LidFace (Autodesk Fusion 360 design; units mm, degrees)
Autodesk Fusion 360 part; units mm, degrees
sketch "Sketch1" plane through (0, 0, 0) normal (0, 1, 0) x (1, 0, 0)
  circle A0 centre (0, 0) radius 10.65
  dimension "d1" = 21.3
  constraint coincident A0.centre origin
  measures "d1" diameter of A0
extrude "Extrude1" add sketch "Sketch1" along normal blind 29.6 makes body 1
sketch "Sketch2" plane through (0, 29.6, 0) normal (0, 1, 0) x (-1, 0, 0)
  circle A0 centre (0, 0) radius 10.65
  circle A1 centre (0, 0) radius 7.15
  dimension "d4" = 14.3
  constraint coincident A0.centre A1.centre
  measures "d4" diameter of A1
extrude "Extrude2" cut sketch "Sketch2" against normal blind 27.6 contours A1 bodies 1
sketch "Sketch3" plane through (0, 29.6, 0) normal (0, 1, 0) x (-1, 0, 0)
  circle A0 centre (0, 0) radius 7.15
  circle A1 centre (0, 0) radius 10.65
  line L0 (0, -10.65) -> (2.4, -10.65)
  line L1 (0, -10.65) -> (-2.4, -10.65)
  line L2 (2.4, -10.65) -> (2.4, -7.1491)
  line L3 (-2.4, -10.65) -> (-2.4, -8)
  line L4 (2.4, -10.65) -> (2.4, -15.65)
  line L5 (-2.4, -10.65) -> (-2.4, -15.65)
  line L6 (2.4, -15.65) -> (-2.4, -15.65)
  dimension "d7" = 2.4
  dimension "d8" = 2.4
  dimension "d9" = 5
  dimension "d10" = 5
  constraint coincident A1 L0.start
  constraint horizontal L0
  constraint horizontal L1
  constraint perpendicular L0 L2
  constraint perpendicular L1 L3
  constraint vertical L4
  constraint vertical L5
  measures "d7" distance of L0.start L0.end
  measures "d8" distance of L0.start L1.end
  measures "d9" distance of L0.end L4.end
  measures "d10" distance of L1.end L5.end
extrude "Extrude3" add sketch "Sketch3" against normal blind 5 contours A1 L1 L3 | A1 L0 L2 | L0 L1 L4 L5 L6 bodies 1
sketch "Sketch4" plane through (2.4, 0, 0) normal (1, 0, 0) x (0, 0, -1)
  line L0 (15.65, 29.6) -> (10.3761, 29.6)
  line L1 (10.3761, 29.6) -> (10.3761, 24.6)
  line L2 (10.3761, 24.6) -> (15.65, 24.6)
  line L3 (15.65, 24.6) -> (15.65, 29.6)
  line L4 (13.013, 29.6) -> (13.013, 27.1)
  circle A0 centre (13.013, 27.1) radius 2.5
  circle A1 centre (13.013, 27.1) radius 1.95
  dimension "d13" = 2.5
  dimension "d14" = 5
  dimension "d15" = 3.9
  constraint midpoint L0 L4.start
  constraint vertical L4
  constraint coincident L4.end A0.centre
  constraint concentric A0 A1
  measures "d13" distance of L4.start L4.end
  measures "d14" diameter of A0
  measures "d15" diameter of A1
sphere "SpherePrimitive1" add diameter 3.9 placed x (0, 0, -1) y (0, 1, 0) z (1, 0, 0) at (2.4, 27.1, -13.013) bodies 1
sketch "Sketch5" plane through (-2.4, 0, 0) normal (-1, 0, 0) x (0, 0, 1)
  line L0 (-10.3761, 29.6) -> (-15.65, 29.6)
  line L1 (-15.65, 29.6) -> (-15.65, 24.6)
  line L2 (-15.65, 24.6) -> (-10.3761, 24.6)
  line L3 (-10.3761, 24.6) -> (-10.3761, 29.6)
  circle A0 centre (-13.013, 27.1) radius 1.95
  point P0 (-13.013, 27.1)
  dimension "d17" = 3.9
  constraint coincident P0 A0.centre
  measures "d17" diameter of A0
sphere "SpherePrimitive2" add diameter 3.9 placed x (0, 0, 1) y (0, 1, 0) z (-1, 0, 0) at (-2.4, 27.1, -13.013) bodies 1
fillet "Fillet1" radius 2.5 2 edges at (0, 29.6, -15.65) (0, 24.6, -15.65) on bodies 1
fillet "Fillet2" radius 2.5 1 edges at (0, 24.6, -10.65) on bodies 1
sketch "Sketch6" plane through (0, 0, 0) normal (0, -1, 0) x (1, 0, 0)
  circle A0 centre (0, 0) radius 10.65
  line L0 (-10.65, 0) -> (10.65, 0)
  line L1 (10.65, 0) -> (10.65, -17.8532)
  line L2 (10.65, -17.8532) -> (-10.65, -17.8532)
  line L3 (-10.65, -17.8532) -> (-10.65, 0)
  point P0 (-10.65, 0)
  dimension "d21" = 21.3
  constraint horizontal L0
  constraint vertical L1
  constraint horizontal L2
  constraint vertical L3
  constraint coincident P0 L0.start
  measures "d21" distance of P0 L0.end
extrude "Extrude4" cut sketch "Sketch6" against normal blind 37 contours A0 L1 L2 L3 | A0 L0 picked at (3.0909, -3.0462) bodies 1
sketch "Sketch7" plane through (0, 0, 0) normal (0, 0, -1) x (-1, 0, 0)
  line L0 (10.65, 29.6) -> (7.15, 29.6)
  line L1 (7.15, 29.6) -> (7.15, 2)
  line L2 (7.15, 2) -> (-7.15, 2)
  line L3 (-10.65, 0) -> (10.65, 0)
  line L4 (10.65, 0) -> (10.65, 29.6)
  line L5 (-10.65, 0) -> (-10.65, 29.6)
  line L6 (-10.65, 0) -> (-10.65, 14.8)
  line L7 (-15.65, 17.475) -> (-10.65, 17.475)
  line L8 (-15.65, 12.125) -> (-10.65, 12.0997)
  line L9 (-15.65, 17.475) -> (-15.65, 19.975)
  line L10 (-15.65, 19.975) -> (-10.65, 19.975)
  line L11 (-15.65, 12.125) -> (-15.65, 9.625)
  line L12 (-15.65, 9.625) -> (-10.65, 9.625)
  point P0 (-10.65, 29.6)
  dimension "d65" = 2.5
  dimension "d66" = 2.5
  dimension "d67" = 5
  constraint coincident L3.start L5.start
  constraint coincident P0 L5.end
  constraint midpoint L5 L6.end
  constraint coincident L5 L7.end
  constraint perpendicular L5 L7
  constraint coincident L6 L8.end
  constraint coincident L5 L10.end
  constraint perpendicular L5 L10
  constraint vertical L11
  constraint horizontal L12
  measures "d65" distance of L7.start L9.end
  measures "d66" distance of L8.start L11.end
  measures "d67" distance of L11.end L12.end
extrude "Extrude7" add sketch "Sketch7" along normal blind 2.5 and the other way blind 2.5 separate body makes body 2 at (12.3167, 12.1081, -0.8333) makes body 3 at (13.9833, 17.475, 0.8333)
sketch "Sketch13" plane through (10.65, 0, 0) normal (-1, 0, 0) x (0, 0, 1)
  line L0 (2.5, 19.975) -> (-2.5, 19.975)
  line L1 (-2.5, 19.975) -> (-2.5, 17.475)
  line L2 (-2.5, 17.475) -> (2.5, 17.475)
  line L3 (2.5, 17.475) -> (2.5, 19.975)
extrude "Extrude8" add sketch "Sketch13" 1 faces at (10.65, 11.2748, -0.8333) along normal blind 1.5 on bodies 2 bodies 2 1 3
sketch "Sketch14" plane through (0, 0, 0) normal (0, 0, -1) x (-1, 0, 0)
  line L0 (-9.15, 9.625) -> (-10.65, 9.625)
  line L1 (-10.65, 9.625) -> (-10.65, 0)
  line L2 (-10.65, 0) -> (10.65, 0)
  line L3 (10.65, 0) -> (10.65, 29.6)
  line L4 (10.65, 29.6) -> (7.15, 29.6)
  line L5 (7.15, 29.6) -> (7.15, 2)
  line L6 (7.15, 2) -> (-7.15, 2)
  line L7 (-7.15, 2) -> (-7.15, 29.6)
  line L8 (-7.15, 29.6) -> (-10.65, 29.6)
  line L9 (-10.65, 29.6) -> (-10.65, 19.975)
  line L10 (-10.65, 19.975) -> (-9.15, 19.975)
  line L11 (-9.15, 19.975) -> (-9.15, 17.475)
  line L12 (-9.15, 17.475) -> (-10.65, 17.475)
  line L13 (-10.65, 17.475) -> (-10.65, 12.0997)
  line L14 (-10.65, 12.0997) -> (-9.15, 12.0997)
  line L15 (-9.15, 12.0997) -> (-9.15, 9.625)
  line L16 (-10.65, 17.475) -> (-10.65, 19.975)
  line L17 (-10.65, 12.0997) -> (-10.65, 9.625)
  constraint coincident L12.end L13.start
  constraint coincident L9.end L10.start
  constraint coincident L13.end L14.start
  constraint coincident L0.end L1.start
extrude "Extrude9" cut sketch "Sketch14" along normal blind 4 bodies 2
sketch "Sketch15" plane through (-0.0609, 12.0456, 0) normal (-0.005055, 0.999987, 0) x (0, 0, 1)
  line L0 (2.5, 15.7111) -> (-2.5, 15.7111)
  line L1 (-2.5, 15.7111) -> (-2.5, 10.711)
  line L2 (-2.5, 10.711) -> (0, 10.711)
  line L3 (0, 10.711) -> (2.5, 10.711)
  line L4 (2.5, 10.711) -> (2.5, 15.7111)
  line L5 (0, 15.7111) -> (0, 10.7995)
  line L6 (-2.5, 13.2111) -> (2.5, 13.2111)
  circle A0 centre (0, 13.2111) radius 2
  circle A1 centre (0, 13.2111) radius 2
  point P0 (0, 10.7995)
  dimension "d77" = 4
  constraint midpoint L0 L5.start
  constraint coincident P0 L5.end
  constraint midpoint L1 L6.start
  constraint midpoint L4 L6.end
  constraint midpoint L6 A0.centre
  constraint concentric A0 A1
  measures "d77" diameter of A0
sketch "Sketch16" plane through (0, 17.475, 0) normal (0, -1, 0) x (1, 0, 0)
  line L0 (10.65, 0) -> (10.65, -2.5)
  line L1 (10.65, -2.5) -> (15.65, -2.5)
  line L2 (15.65, -2.5) -> (15.65, 2.5)
  line L3 (15.65, 2.5) -> (10.3524, 2.5)
  arc A0 (10.65, 0) -> (10.3524, 2.5) centre (0, 0) ccw
  line L4 (15.65, 0) -> (10.65, 0)
  line L5 (13.15, 0) -> (13.15, -2.5)
  circle A1 centre (13.15, 0) radius 2
  dimension "d79" = 4
  constraint midpoint L2 L4.start
  constraint coincident L0.start A0.start
  constraint midpoint L4 L5.start
  constraint midpoint L1 L5.end
  constraint coincident L5.start A1.centre
  measures "d79" diameter of A1
fillet "Fillet9" radius 2.5 6 edges at (10.65, 18.725, -2.5) (15.65, 18.725, -2.5) (15.65, 18.725, 2.5) (10.65, 10.8624, -2.5) (15.65, 10.875, -2.5) (15.65, 10.875, 2.5) on bodies 2
fillet "Fillet10" radius 4 2 edges at (10.3524, 10.8624, 2.5) (10.3524, 18.725, 2.5) on bodies 2
sketch "Sketch17" plane through (0, 17.475, 0) normal (0, -1, 0) x (1, 0, 0)
  arc A0 (10.65, 0) -> (13.15, 2.5) centre (13.15, 0) ccw
  line L0 (13.15, 2.5) -> (13.1291, 2.5)
  arc A1 (9.5443, 4.7253) -> (13.1291, 2.5) centre (13.1291, 6.5) ccw
  arc A2 (10.65, 0) -> (9.5443, 4.7253) centre (0, 0) ccw
  line L1 (13.15, 0) -> (13.15, 4.3041)
  line L2 (13.15, 0) -> (12.15, 0)
  line L3 (13.15, 0) -> (14.15, 0)
  line L4 (12.15, 0) -> (12.15, 4.5558)
  line L5 (14.15, 0) -> (14.15, 3.8126)
  dimension "d83" = 1
  dimension "d84" = 1
  constraint coincident A0.centre L1.start
  constraint vertical L1
  constraint horizontal L2
  constraint horizontal L3
  constraint perpendicular L2 L4
  constraint perpendicular L3 L5
  measures "d83" distance of A0.centre L2.end
  measures "d84" distance of A0.centre L3.end
sketch "Sketch18" plane through (-0.0609, 12.0456, 0) normal (-0.005055, 0.999987, 0) x (0, 0, 1)
  ellipse E0 centre (0, 13.2111) end of major axis (0, 15.7111) minor radius 2.5 (2.5, 13.2111) -> (0, 10.711) ccw
  line L0 (0, 10.711) -> (3.3609, 10.711)
  ellipse E1 centre (6.5, 13.1901) end of major axis (6.5, 9.1901) minor radius 4 (2.5, 13.1901) -> (3.3609, 10.711) ccw
  line L1 (2.5, 13.1901) -> (2.5, 13.2111)
  line L2 (0, 13.2111) -> (3.5488, 13.2111)
  line L3 (0, 13.2111) -> (0, 12.2111)
  line L4 (0, 13.2111) -> (0, 14.2111)
  line L5 (0, 14.2111) -> (4.5543, 14.2361)
  line L6 (0, 12.2111) -> (4.6288, 12.2111)
  point P0 (0, 13.2121)
  point P1 (0, 13.2121)
  dimension "d87" = 1
  dimension "d88" = 1
  constraint coincident E0.centre L2.start
  constraint horizontal L2
  constraint vertical L3
  constraint vertical L4
  constraint perpendicular L3 L6
  measures "d87" distance of E0.centre L3.end
  measures "d88" distance of E0.centre L4.end
sketch "Sketch19" plane through (0, 29.6, 0) normal (0, 1, 0) x (-1, 0, 0)
  line L0 (7.15, 0) -> (10.65, 0)
  arc A0 (10.65, 0) -> (-10.65, 0) centre (0, 0) ccw
  line L1 (-10.65, 0) -> (-7.15, 0)
  arc A1 (7.15, 0) -> (-7.15, 0) centre (0, 0) ccw
  line L2 (0, 10.65) -> (0, 8.65)
  circle A2 centre (0, 0) radius 8.65
  dimension "d92" = 2
  constraint midpoint A0 L2.start
  constraint vertical L2
  constraint concentric A0 A2
  constraint coincident L2.end A2
  measures "d92" distance of L2.start L2.end
extrude "Extrude12" add sketch "Sketch19" along normal blind 44 contours L0 A0 L2 A2 | A0 L1 L2 A2 bodies 2
sketch "sketch" plane through (0, 73.6, 0) normal (0, 1, 0) x (-1, 0, 0)
  circle A0 centre (-9.5314, -1.5) radius 0.625
  circle A1 centre (0, -9.65) radius 0.625
  arc A2 (-8.65, 0) -> (8.65, 0) centre (0, 0) ccw
  line L0 (9.65, -1.5) -> (8.519, -1.5)
  line L1 (8.519, -1.5) -> (9.5315, -1.5)
  line L2 (0, -1.5) -> (0, -10.65)
  circle A3 centre (9.5315, -1.5) radius 0.625
  line L3 (9.5315, -1.5) -> (9.5315, 0.0003)
  line L4 (-10.5438, -1.5) -> (10.5438, -1.5)
  line L5 (0, -10.65) -> (0, -9.65)
  line L6 (-10.65, 0) -> (-8.65, 0)
  line L7 (8.519, -1.5) -> (10.5438, -1.5)
  arc A4 (10.65, 0) -> (-10.65, 0) centre (0, 0) cw
  line L8 (8.65, 0) -> (10.65, 0)
  line L9 (-9.5314, -1.5) -> (-9.5314, 0)
  line L10 (10.5438, -1.5) -> (0, -1.5)
  line L11 (-10.5438, -1.5) -> (-8.519, -1.5)
  line L12 (9.65, -1.5) -> (10.5438, -1.5)
sketch "Sketch21" plane through (0, 73.6, 0) normal (0, 1, 0) x (-1, 0, 0)
  arc A0 (10.65, 0) -> (-10.65, 0) centre (0, 0) ccw
  line L0 (-10.65, 0) -> (-8.65, 0)
  arc A1 (8.65, 0) -> (-8.65, 0) centre (0, 0) ccw
  line L1 (8.65, 0) -> (10.65, 0)
  line L2 (9.5315, 0.0003) -> (9.5315, 1.5003)
  circle A2 centre (9.5315, 1.5003) radius 0.625
  line L3 (0, 0) -> (0, 10.65)
  line L4 (0, 10.65) -> (0, 9.65)
  circle A3 centre (0, 9.65) radius 0.625
  line L5 (-9.5314, 0) -> (-9.5314, 1.5)
  circle A4 centre (-9.5314, 1.5) radius 0.625
  point P0 (9.5315, 0.0003)
  point P1 (-9.5314, 0)
  dimension "d95" = 1.5
  dimension "d96" = 1.25
  dimension "d97" = 1
  dimension "d98" = 1.25
  dimension "d99" = 1.5
  dimension "d100" = 1.25
  constraint coincident P0 L2.start
  constraint vertical L2
  constraint coincident L2.end A2.centre
  constraint coincident A0.centre A1.centre
  constraint midpoint A0 L3.end
  constraint vertical L4
  constraint coincident L4.end A3.centre
  constraint coincident P1 L5.start
  constraint vertical L5
  constraint coincident L5.end A4.centre
  measures "d95" distance of P0 L2.end
  measures "d96" diameter of A2
  measures "d97" distance of L3.end L4.end
  measures "d98" diameter of A3
  measures "d99" distance of P1 L5.end
  measures "d100" diameter of A4
sphere "SpherePrimitive9" add diameter 1.25 placed x (-1, 0, 0) y (0, 0, 1) z (0, 1, 0) at (-9.5315, 73.6, 1.5003) bodies 2
sphere "SpherePrimitive10" add diameter 1.25 placed x (-1, 0, 0) y (0, 0, 1) z (0, 1, 0) at (0, 73.6, 9.65) bodies 2
sphere "SpherePrimitive11" add diameter 1.25 placed x (-1, 0, 0) y (0, 0, 1) z (0, 1, 0) at (9.5314, 73.6, 1.5) bodies 2
sketch "Sketch22" plane through (0, 0, 0) normal (0, 0, -1) x (-1, 0, 0)
  line L0 (-10.65, 9.625) -> (-10.65, 0)
  line L1 (-10.65, 0) -> (10.65, 0)
  line L2 (10.65, 0) -> (10.65, 73.6)
  line L3 (10.65, 73.6) -> (8.65, 73.6)
  line L4 (8.65, 73.6) -> (8.65, 29.6)
  line L5 (8.65, 29.6) -> (7.15, 29.6)
  line L6 (7.15, 29.6) -> (7.15, 2)
  line L7 (7.15, 2) -> (-7.15, 2)
  line L8 (-7.15, 2) -> (-7.15, 29.6)
  line L9 (-7.15, 29.6) -> (-8.65, 29.6)
  line L10 (-8.65, 29.6) -> (-8.65, 73.6)
  line L11 (-8.65, 73.6) -> (-10.65, 73.6)
  line L12 (-10.65, 73.6) -> (-10.65, 19.975)
  line L13 (-10.65, 19.975) -> (-10.65, 17.475)
  line L14 (-10.65, 17.475) -> (-10.65, 12.0997)
  line L15 (-10.65, 12.0997) -> (-10.65, 9.625)
  line L16 (8.65, 29.6) -> (12, 29.6)
  line L17 (9.65, 73.6) -> (9.65, 29.6)
  line L18 (9.65, 51.6) -> (14, 51.6)
  circle A0 centre (9.65, 51.6) radius 0.5
  dimension "d104" = 1
  constraint coincident L4.end L5.start
  constraint perpendicular L2 L16
  constraint midpoint L3 L17.start
  constraint coincident L16 L17.end
  constraint perpendicular L16 L17
  constraint midpoint L17 L18.start
  constraint perpendicular L2 L18
  constraint coincident L18.start A0.centre
  measures "d104" diameter of A0
extrude "Extrude13" add sketch "Sketch22" along normal blind 1.2 contours L17 L18 A0 | L17 L18 A0 | L17 A0 bodies 2
fillet "Fillet12" radius 0.25 1 edges at (-9.1838, 51.4192, -1.2) on bodies 2
sketch "Sketch23" plane through (0, 73.6, 0) normal (0, 1, 0) x (-1, 0, 0)
  circle A0 centre (-9.5314, 1.5) radius 0.625
  circle A1 centre (0, 9.65) radius 0.625
  circle A2 centre (9.5315, 1.5003) radius 0.625
  arc A3 (10.65, 0) -> (-10.65, 0) centre (0, 0) ccw
  line L0 (-10.65, 0) -> (-8.65, 0)
  arc A4 (8.65, 0) -> (-8.65, 0) centre (0, 0) ccw
  line L1 (8.65, 0) -> (10.65, 0)
sketch "Sketch24" plane through (0, 0, 0) normal (0, 0, -1) x (-1, 0, 0)
  circle A0 centre (9.65, 51.6) radius 0.5
  line L0 (-10.65, 9.625) -> (-10.65, 0)
  line L1 (-10.65, 0) -> (10.65, 0)
  line L2 (10.65, 0) -> (10.65, 73.6)
  line L3 (10.65, 73.6) -> (8.65, 73.6)
  line L4 (8.65, 73.6) -> (8.65, 29.6)
  line L5 (8.65, 29.6) -> (7.15, 29.6)
  line L6 (7.15, 29.6) -> (7.15, 2)
  line L7 (7.15, 2) -> (-7.15, 2)
  line L8 (-7.15, 2) -> (-7.15, 29.6)
  line L9 (-7.15, 29.6) -> (-8.65, 29.6)
  line L10 (-8.65, 29.6) -> (-8.65, 73.6)
  line L11 (-8.65, 73.6) -> (-10.65, 73.6)
  line L12 (-10.65, 73.6) -> (-10.65, 19.975)
  line L13 (-10.65, 19.975) -> (-10.65, 17.475)
  line L14 (-10.65, 17.475) -> (-10.65, 12.0997)
  line L15 (-10.65, 12.0997) -> (-10.65, 9.625)
sketch "Sketch25" plane through (0, 9.625, 0) normal (0, -1, 0) x (1, 0, 0)
  arc A0 (10.65, 0) -> (13.15, 2.5) centre (13.15, 0) ccw
  line L0 (13.15, 2.5) -> (13.1291, 2.5)
  arc A1 (9.5443, 4.7253) -> (13.1291, 2.5) centre (13.1291, 6.5) ccw
  arc A2 (10.65, 0) -> (9.5443, 4.7253) centre (0, 0) ccw
  circle A3 centre (13.15, 0) radius 1.1
  dimension "d112" = 2.2
  constraint concentric A0 A3
  measures "d112" diameter of A3
extrude "Extrude14" cut sketch "Sketch25" against normal blind 10.35 contours A3 bodies 2
chamfer "Chamfer2" distance 0.5 angle 45 2 edges at (12.1244, 19.975, -0.3978) (12.1244, 9.625, 0.3978) tangent chain off on bodies 2
sketch "Sketch26" plane through (-0.0609, 12.0456, 0) normal (-0.005055, 0.999987, 0) x (0, 0, 1)
  ellipse E0 centre (0, 13.2111) end of major axis (0, 14.3111) minor radius 1.1
  ellipse E1 centre (0, 13.2111) end of major axis (0, 15.7111) minor radius 2.5 (2.5, 13.2111) -> (0, 10.711) ccw
  line L0 (0, 10.711) -> (3.3609, 10.711)
  ellipse E2 centre (6.5, 13.1901) end of major axis (6.5, 9.1901) minor radius 4 (2.5, 13.1901) -> (3.3609, 10.711) ccw
  line L1 (2.5, 13.1901) -> (2.5, 13.2111)
extrude "Extrude15" add sketch "Sketch26" along normal blind 0.15 bodies 2
sketch "Sketch27" plane through (0, 17.475, 0) normal (0, -1, 0) x (1, 0, 0)
  circle A0 centre (13.15, 0) radius 1.1
  arc A1 (10.65, 0) -> (13.15, 2.5) centre (13.15, 0) ccw
  line L0 (13.15, 2.5) -> (13.1291, 2.5)
  arc A2 (9.5443, 4.7253) -> (13.1291, 2.5) centre (13.1291, 6.5) ccw
  arc A3 (10.65, 0) -> (9.5443, 4.7253) centre (0, 0) ccw
extrude "Extrude16" add sketch "Sketch27" along normal blind 0.15 separate body makes body 4
sketch "Sketch28" plane through (0, 12.0997, 0) normal (0, 1, 0) x (-1, 0, 0)
  arc A0 (-9.5443, 4.7253) -> (-10.65, 0) centre (0, 0) ccw
  arc A1 (-10.65, 3.3609) -> (-9.5443, 4.7253) centre (-13.1291, 6.5) ccw
  line L0 (-10.65, 3.3609) -> (-10.65, 0)
extrude "Extrude17" add sketch "Sketch28" along normal blind 0.149 bodies 2
fillet "Fillet13" [suppressed]
fillet "Fillet14" [suppressed]
fillet "Fillet15" [suppressed]
fillet "Fillet16" [suppressed]
